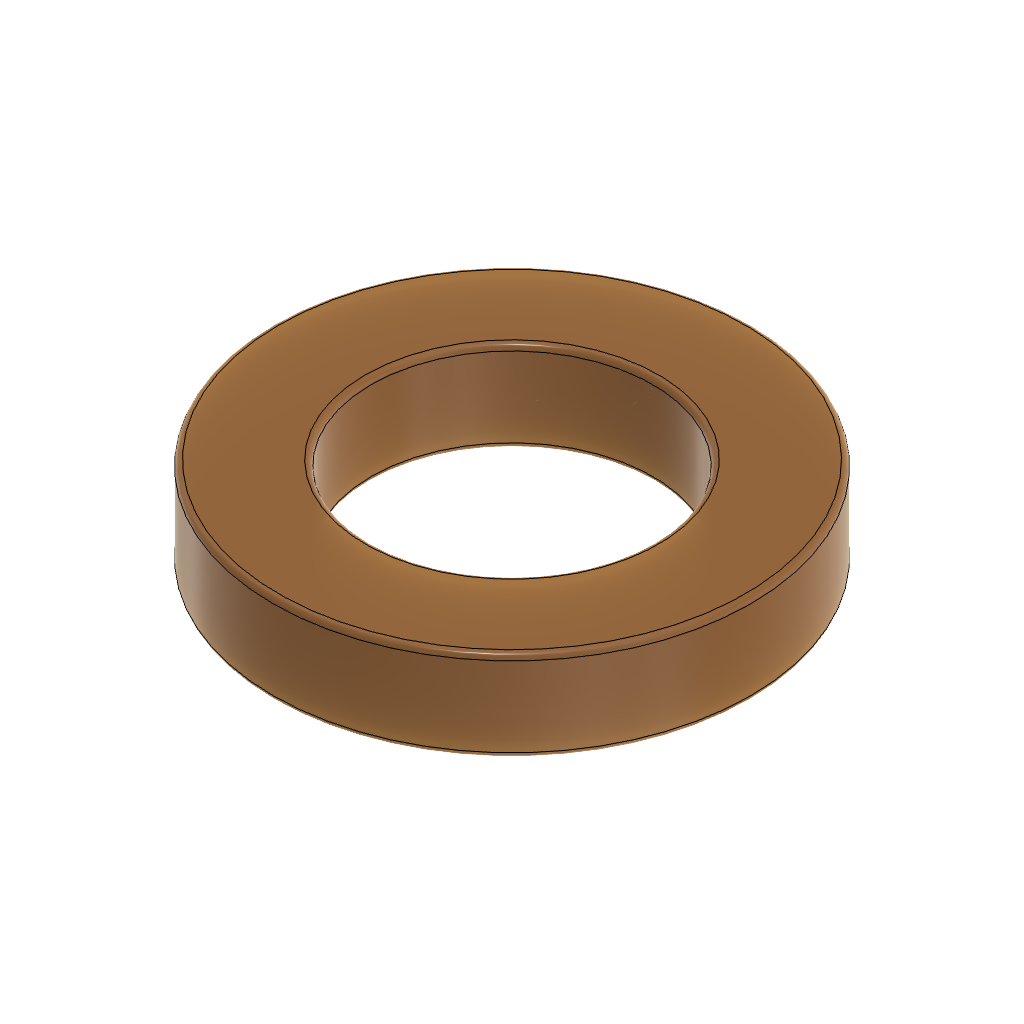
spacer_crank (Autodesk Fusion 360 design; units mm, degrees)
part number: 2026-10-03-17-55-37-116
Autodesk Fusion 360 part; units mm, degrees
sketch "Sketch1" plane through (0, 0, 0) normal (0, 0, 1) x (1, 0, 0)
  circle A0 centre (0, 0) radius 6.2
  circle A1 centre (0, 0) radius 10.5
  dimension "d1" = 12.4
  dimension "d2" = 21
  constraint coincident A0.centre A1.centre
  constraint concentric A0 A1
  measures "d1" diameter of A0
  measures "d2" diameter of A1
extrude "Extrude1" add sketch "Sketch1" along normal blind 4
fillet "Fillet1" radius 0.25 4 edges at (-5.7804, 2.242, 4) (-5.7804, 2.242, 0) (-9.7894, -3.797, 4) (-9.7894, -3.797, 0)
